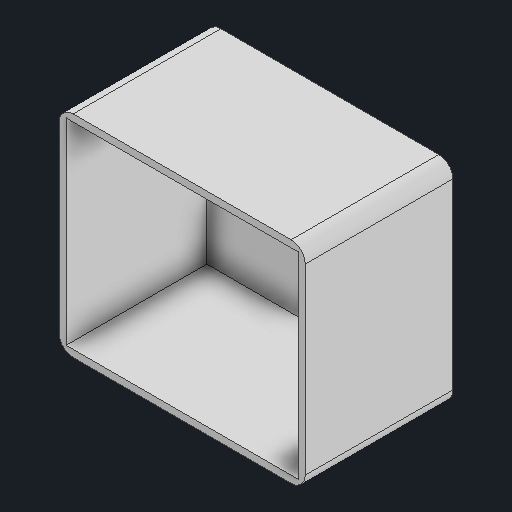
# Autodesk Inventor part: base
Saved by Autodesk Inventor 2027 (Build 310192060, 192F)
## iProperties
Created: 2026-09-17
Part Number: base
Material: Genérico
Document SubType Name: Modeling
Designer: Bolivar A.
Density: 1 g/cm^3
Appearance: Valor por defecto
Project: STAR TRACKER
Author: alexa
Title: Base
Autodesk Inventor part; units mm, degrees
ref_plane "YZ Plane" through (0, 0, 0) normal (1, 0, 0) x (0, 1, 0)
ref_plane "XZ Plane" through (0, 0, 0) normal (0, 1, 0) x (-1, 0, 0)
ref_plane "XY Plane" through (0, 0, 0) normal (0, 0, 1) x (1, 0, 0)
sketch "Boceto1" plane through (0, 0, 0) normal (0, 0, 1) x (1, 0, 0)
  line L0 (-35, 30) -> (35, 30)
  line L1 (35, 30) -> (35, -30)
  line L2 (35, -30) -> (-35, -30)
  line L3 (-35, -30) -> (-35, 30)
  point P0 (0, 0)
  point P1 (-35, 0)
  point P2 (0, -30)
  dimension "d0" = 70
  dimension "d1" = 60
  constraints: 8 end point, 2 midpoint, 2 parallel, 1 horizontal, 1 horizontal alignment, 1 perpendicular, 1 vertical alignment
  measures "d0" distance of L1.end L2.end
  measures "d1" distance of L0.end L1.end
extrude "Extrusión1" add sketch "Boceto1" along normal blind 2
sketch "Boceto3" plane through (0, 0, 2) normal (0, 0, 1) x (1, 0, 0)
  line L0 (-35, -30) -> (35, -30) projected
  line L1 (35, -30) -> (35, 30) projected
  line L2 (35, 30) -> (-35, 30) projected
  line L3 (-35, 30) -> (-35, -30) projected
  line L4 (-33, -28) -> (33, -28)
  line L5 (33, -28) -> (33, 28)
  line L6 (33, 28) -> (-33, 28)
  line L7 (-33, 28) -> (-33, -28)
  point P0 (0, 0)
  dimension "d13" = 2
  constraints: 8 end point, 3 other
  measures "d13" distance between parallel lines of L3 L7
extrude "Extrusión3" add sketch "Boceto3" along normal blind 40
sketch "Boceto4" plane through (0, 0, 0) normal (0, 0, -1) x (-1, 0, 0)
  arc A0 (19.55, -10) -> (20.15, -9.4) centre (19.55, -9.4) ccw projected
  line L0 (20.15, -3.4117) -> (20.15, -9.4) projected
  line L1 (20.15, 0) -> (20.15, -3.4117) projected
  line L2 (20.15, 3.4117) -> (20.15, 0) projected
  line L3 (20.15, 9.4) -> (20.15, 3.4117) projected
  arc A1 (20.15, 9.4) -> (19.55, 10) centre (19.55, 9.4) ccw projected
  line L4 (10.15, 10) -> (19.55, 10) projected
  line L5 (-13.9922, 10) -> (10.15, 10) projected
  line L6 (-19.55, 10) -> (-13.9922, 10) projected
  arc A2 (-19.55, 10) -> (-20.15, 9.4) centre (-19.55, 9.4) ccw projected
  line L7 (-20.15, -9.4) -> (-20.15, 9.4) projected
  arc A3 (-20.15, -9.4) -> (-19.55, -10) centre (-19.55, -9.4) ccw projected
  line L8 (-13.9922, -10) -> (-19.55, -10) projected
  line L9 (10.15, -10) -> (-13.9922, -10) projected
  line L10 (19.55, -10) -> (10.15, -10) projected
  arc A4 (26.2, -2.544) -> (26.2, -6.456) centre (25.15, -4.5) ccw projected
  arc A5 (26.2, 6.456) -> (26.2, 2.544) centre (25.15, 4.5) ccw projected
  arc A6 (-26.2, 2.544) -> (-26.2, 6.456) centre (-25.15, 4.5) ccw projected
  arc A7 (-26.2, -6.456) -> (-26.2, -2.544) centre (-25.15, -4.5) ccw projected
  line L11 (-13.9922, -10.5) -> (-19.55, -10.5)
  arc A8 (-20.65, -9.4) -> (-19.55, -10.5) centre (-19.55, -9.4) ccw
  line L12 (-20.65, -9.4) -> (-20.65, 9.4)
  arc A9 (-19.55, 10.5) -> (-20.65, 9.4) centre (-19.55, 9.4) ccw
  line L13 (-19.55, 10.5) -> (-13.9922, 10.5)
  line L14 (-13.9922, 10.5) -> (10.15, 10.5)
  line L15 (10.15, 10.5) -> (19.55, 10.5)
  arc A10 (20.65, 9.4) -> (19.55, 10.5) centre (19.55, 9.4) ccw
  line L16 (20.65, 9.4) -> (20.65, 3.4117)
  line L17 (20.65, 3.4117) -> (20.65, 0)
  line L18 (20.65, 0) -> (20.65, -3.4117)
  line L19 (20.65, -3.4117) -> (20.65, -9.4)
  arc A11 (19.55, -10.5) -> (20.65, -9.4) centre (19.55, -9.4) ccw
  line L20 (19.55, -10.5) -> (10.15, -10.5)
  line L21 (10.15, -10.5) -> (-13.9922, -10.5)
  circle A12 centre (25.15, -4.5) radius 2
  circle A13 centre (25.15, 4.5) radius 2
  circle A14 centre (-25.15, -4.5) radius 2
  circle A15 centre (-25.15, 4.5) radius 2
  point P0 (0, 0)
  dimension "d16" = 0.5
  dimension "d17" = 4
  dimension "d18" = 4
  dimension "d19" = 4
  dimension "d20" = 4
  constraints: 22 end point, 8 centre point, 8 point on circle, 4 coincident, 14 other
  measures "d16" distance between parallel lines of L9 L21
  measures "d17" diameter of A12
  measures "d18" diameter of A13
  measures "d19" diameter of A14
  measures "d20" diameter of A15
extrude "Extrusión4" cut sketch "Boceto4" against normal blind 40 contours L10 L9 L8 A3 L7 A2 L6 L5 L4 A1 L3 L2 L1 L0 A0 | L11 A8 L12 A9 L13 L14 L15 A10 L16 L17 L18 L19 A11 L20 L21 | A12 | A13 | A14 | A15
fillet "Empalme1" radius 4 4 edges at (-35, -30, 21) (35, -30, 21) (-35, 30, 21) (35, 30, 21)
